Autodesk Fusion 360 part; units mm, degrees
(part 2 of 3)
sketch "X02_add_gear (2)" plane through (-4.75, 0, 0) normal (1, 0, 0) x (0, 0, -1) in component "OuterKnuckle_R"
  line L0 (-54.905, -30.601) -> (-49.6957, -2.7337)
  arc A0 (-49.6957, -2.7337) -> (-50.6618, -2.5703) centre (-54.905, -30.601) ccw
  line L1 (-50.6618, -2.5703) -> (-50.6013, -2.1703)
  spline S0 degree 5 poles (-50.6013, -2.1703) (-50.5993, -2.1455) (-50.5958, -2.0959) (-50.5916, -2.0214) (-50.5878, -1.9219) (-50.5864, -1.7973) (-50.5883, -1.6723) (-50.5934, -1.547) (-50.6015, -1.4215) (-50.6125, -1.2957) (-50.626, -1.1698) (-50.6418, -1.0437) (-50.6597, -0.9176) (-50.6793, -0.7914) (-50.7007, -0.6651) (-50.7237, -0.5388) (-50.7485, -0.4126) (-50.7749, -0.2863) (-50.8029, -0.1599) (-50.8327, -0.0336) (-50.864, 0.0927) (-50.8969, 0.219) (-50.9313, 0.3452) (-50.9671, 0.4714) (-51.0044, 0.5975) (-51.043, 0.7236) (-51.0829, 0.8496) (-51.1242, 0.9755) (-51.1669, 1.1013) (-51.2109, 1.227) (-51.2562, 1.3526) (-51.2934, 1.453) (-51.322, 1.5283) (-51.3413, 1.5784) (-51.351, 1.6035) knots 0 0 0 0 0 0 0.033333 0.066667 0.1 0.133333 0.166667 0.2 0.233333 0.266667 0.3 0.333333 0.366667 0.4 0.433333 0.466667 0.5 0.533333 0.566667 0.6 0.633333 0.666667 0.7 0.733333 0.766667 0.8 0.833333 0.866667 0.9 0.933333 0.966667 1 1 1 1 1 1
  arc A1 (-51.351, 1.6035) -> (-52.481, 1.7082) centre (-54.905, -30.601) ccw
  spline S1 degree 5 poles (-52.481, 1.7082) (-52.4951, 1.6853) (-52.5233, 1.6396) (-52.5652, 1.5708) (-52.6203, 1.479) (-52.6879, 1.3638) (-52.7542, 1.2484) (-52.8192, 1.1325) (-52.883, 1.0164) (-52.9454, 0.8999) (-53.0065, 0.7831) (-53.0663, 0.6659) (-53.1247, 0.5485) (-53.1817, 0.4307) (-53.2372, 0.3126) (-53.2912, 0.1942) (-53.3437, 0.0755) (-53.3945, -0.0435) (-53.4437, -0.1628) (-53.4912, -0.2824) (-53.537, -0.4023) (-53.5812, -0.5225) (-53.6237, -0.6429) (-53.6644, -0.7637) (-53.7032, -0.8847) (-53.7396, -1.006) (-53.7735, -1.1276) (-53.8046, -1.2495) (-53.8326, -1.3717) (-53.8574, -1.4942) (-53.8789, -1.617) (-53.8935, -1.7155) (-53.903, -1.7895) (-53.9087, -1.8389) (-53.9113, -1.8636) knots 0 0 0 0 0 0 0.033333 0.066667 0.1 0.133333 0.166667 0.2 0.233333 0.266667 0.3 0.333333 0.366667 0.4 0.433333 0.466667 0.5 0.533333 0.566667 0.6 0.633333 0.666667 0.7 0.733333 0.766667 0.8 0.833333 0.866667 0.9 0.933333 0.966667 1 1 1 1 1 1
  line L2 (-53.9113, -1.8636) -> (-53.9253, -2.2679)
  arc A2 (-53.9253, -2.2679) -> (-55.8847, -2.2679) centre (-54.905, -30.601) ccw
  line L3 (-55.8847, -2.2679) -> (-55.8987, -1.8636)
  spline S2 degree 5 poles (-55.8987, -1.8636) (-55.9013, -1.8389) (-55.907, -1.7895) (-55.9165, -1.7155) (-55.9311, -1.617) (-55.9526, -1.4942) (-55.9774, -1.3717) (-56.0054, -1.2495) (-56.0365, -1.1276) (-56.0704, -1.006) (-56.1068, -0.8847) (-56.1456, -0.7637) (-56.1863, -0.6429) (-56.2288, -0.5225) (-56.273, -0.4023) (-56.3188, -0.2824) (-56.3663, -0.1628) (-56.4155, -0.0435) (-56.4663, 0.0755) (-56.5188, 0.1942) (-56.5728, 0.3126) (-56.6283, 0.4307) (-56.6853, 0.5485) (-56.7437, 0.6659) (-56.8035, 0.7831) (-56.8646, 0.8999) (-56.927, 1.0164) (-56.9908, 1.1325) (-57.0558, 1.2484) (-57.1221, 1.3638) (-57.1897, 1.479) (-57.2448, 1.5708) (-57.2867, 1.6396) (-57.3149, 1.6853) (-57.329, 1.7082) knots 0 0 0 0 0 0 0.033333 0.066667 0.1 0.133333 0.166667 0.2 0.233333 0.266667 0.3 0.333333 0.366667 0.4 0.433333 0.466667 0.5 0.533333 0.566667 0.6 0.633333 0.666667 0.7 0.733333 0.766667 0.8 0.833333 0.866667 0.9 0.933333 0.966667 1 1 1 1 1 1
  arc A3 (-57.329, 1.7082) -> (-58.459, 1.6035) centre (-54.905, -30.601) ccw
  spline S3 degree 5 poles (-58.459, 1.6035) (-58.4687, 1.5784) (-58.488, 1.5283) (-58.5166, 1.453) (-58.5538, 1.3526) (-58.5991, 1.227) (-58.6431, 1.1013) (-58.6858, 0.9755) (-58.7271, 0.8496) (-58.767, 0.7236) (-58.8056, 0.5975) (-58.8429, 0.4714) (-58.8787, 0.3452) (-58.9131, 0.219) (-58.946, 0.0927) (-58.9773, -0.0336) (-59.0071, -0.1599) (-59.0351, -0.2863) (-59.0615, -0.4126) (-59.0863, -0.5388) (-59.1093, -0.6651) (-59.1307, -0.7914) (-59.1503, -0.9176) (-59.1682, -1.0437) (-59.184, -1.1698) (-59.1975, -1.2957) (-59.2085, -1.4215) (-59.2166, -1.547) (-59.2217, -1.6723) (-59.2236, -1.7973) (-59.2222, -1.9219) (-59.2184, -2.0214) (-59.2142, -2.0959) (-59.2107, -2.1455) (-59.2087, -2.1703) knots 0 0 0 0 0 0 0.033333 0.066667 0.1 0.133333 0.166667 0.2 0.233333 0.266667 0.3 0.333333 0.366667 0.4 0.433333 0.466667 0.5 0.533333 0.566667 0.6 0.633333 0.666667 0.7 0.733333 0.766667 0.8 0.833333 0.866667 0.9 0.933333 0.966667 1 1 1 1 1 1
  line L4 (-59.2087, -2.1703) -> (-59.1482, -2.5703)
  arc A4 (-59.1482, -2.5703) -> (-61.0742, -2.9304) centre (-54.905, -30.601) ccw
  line L5 (-61.0742, -2.9304) -> (-61.1622, -2.5355)
  spline S4 degree 5 poles (-61.1622, -2.5355) (-61.1694, -2.5117) (-61.184, -2.4642) (-61.207, -2.3932) (-61.2394, -2.299) (-61.2832, -2.1823) (-61.3301, -2.0664) (-61.38, -1.9514) (-61.433, -1.8373) (-61.4886, -1.724) (-61.5467, -1.6115) (-61.607, -1.4996) (-61.6692, -1.3884) (-61.7332, -1.2779) (-61.7987, -1.1679) (-61.8658, -1.0584) (-61.9345, -0.9496) (-62.0047, -0.8414) (-62.0765, -0.7337) (-62.1499, -0.6267) (-62.2247, -0.5202) (-62.301, -0.4144) (-62.3787, -0.3091) (-62.4577, -0.2043) (-62.538, -0.1002) (-62.6195, 0.0034) (-62.7023, 0.1065) (-62.7863, 0.209) (-62.8715, 0.3109) (-62.9579, 0.4122) (-63.0455, 0.5129) (-63.1166, 0.5931) (-63.1703, 0.653) (-63.2064, 0.6928) (-63.2246, 0.7127) knots 0 0 0 0 0 0 0.033333 0.066667 0.1 0.133333 0.166667 0.2 0.233333 0.266667 0.3 0.333333 0.366667 0.4 0.433333 0.466667 0.5 0.533333 0.566667 0.6 0.633333 0.666667 0.7 0.733333 0.766667 0.8 0.833333 0.866667 0.9 0.933333 0.966667 1 1 1 1 1 1
  arc A5 (-63.2246, 0.7127) -> (-64.3161, 0.4021) centre (-54.905, -30.601) ccw
  spline S5 degree 5 poles (-64.3161, 0.4021) (-64.321, 0.3757) (-64.3308, 0.3228) (-64.345, 0.2436) (-64.3632, 0.138) (-64.3846, 0.0062) (-64.4047, -0.1254) (-64.4236, -0.2569) (-64.441, -0.3882) (-64.4572, -0.5194) (-64.4719, -0.6504) (-64.4854, -0.7812) (-64.4974, -0.9119) (-64.508, -1.0423) (-64.5171, -1.1725) (-64.5247, -1.3024) (-64.5307, -1.432) (-64.5351, -1.5613) (-64.5379, -1.6903) (-64.539, -1.819) (-64.5384, -1.9474) (-64.5362, -2.0754) (-64.5324, -2.2031) (-64.5267, -2.3304) (-64.5191, -2.4572) (-64.5093, -2.5835) (-64.4969, -2.7091) (-64.4819, -2.834) (-64.4638, -2.958) (-64.4427, -3.0812) (-64.4184, -3.2035) (-64.3965, -3.3006) (-64.3786, -3.3731) (-64.366, -3.4212) (-64.3596, -3.4452) knots 0 0 0 0 0 0 0.033333 0.066667 0.1 0.133333 0.166667 0.2 0.233333 0.266667 0.3 0.333333 0.366667 0.4 0.433333 0.466667 0.5 0.533333 0.566667 0.6 0.633333 0.666667 0.7 0.733333 0.766667 0.8 0.833333 0.866667 0.9 0.933333 0.966667 1 1 1 1 1 1
  line L6 (-64.3596, -3.4452) -> (-64.2266, -3.8273)
  arc A6 (-64.2266, -3.8273) -> (-66.0536, -4.5351) centre (-54.905, -30.601) ccw
  line L7 (-66.0536, -4.5351) -> (-66.2127, -4.1631)
  spline S6 degree 5 poles (-66.2127, -4.1631) (-66.2241, -4.141) (-66.2473, -4.097) (-66.2828, -4.0314) (-66.332, -3.9449) (-66.3965, -3.8381) (-66.4639, -3.7329) (-66.5341, -3.629) (-66.6071, -3.5266) (-66.6827, -3.4254) (-66.7605, -3.3255) (-66.8403, -3.2266) (-66.9219, -3.1288) (-67.005, -3.0318) (-67.0896, -2.9357) (-67.1757, -2.8405) (-67.2632, -2.7461) (-67.3521, -2.6526) (-67.4425, -2.56) (-67.5343, -2.4683) (-67.6274, -2.3774) (-67.7219, -2.2874) (-67.8176, -2.1981) (-67.9145, -2.1097) (-68.0125, -2.022) (-68.1117, -1.9352) (-68.212, -1.8491) (-68.3134, -1.7638) (-68.4159, -1.6793) (-68.5195, -1.5956) (-68.6241, -1.5126) (-68.7086, -1.4469) (-68.7725, -1.3979) (-68.8153, -1.3654) (-68.8368, -1.3492) knots 0 0 0 0 0 0 0.033333 0.066667 0.1 0.133333 0.166667 0.2 0.233333 0.266667 0.3 0.333333 0.366667 0.4 0.433333 0.466667 0.5 0.533333 0.566667 0.6 0.633333 0.666667 0.7 0.733333 0.766667 0.8 0.833333 0.866667 0.9 0.933333 0.966667 1 1 1 1 1 1
  arc A7 (-68.8368, -1.3492) -> (-69.8526, -1.8551) centre (-54.905, -30.601) ccw
  spline S7 degree 5 poles (-69.8526, -1.8551) (-69.8526, -1.882) (-69.8525, -1.9357) (-69.8519, -2.0162) (-69.8504, -2.1233) (-69.8473, -2.2568) (-69.8429, -2.3899) (-69.8372, -2.5226) (-69.8302, -2.6549) (-69.822, -2.7868) (-69.8125, -2.9183) (-69.8016, -3.0494) (-69.7894, -3.18) (-69.7759, -3.3101) (-69.7609, -3.4398) (-69.7445, -3.5689) (-69.7266, -3.6974) (-69.7072, -3.8253) (-69.6862, -3.9526) (-69.6636, -4.0793) (-69.6395, -4.2054) (-69.6138, -4.3308) (-69.5865, -4.4556) (-69.5576, -4.5797) (-69.5268, -4.703) (-69.4939, -4.8253) (-69.4587, -4.9465) (-69.421, -5.0665) (-69.3805, -5.1851) (-69.3371, -5.3024) (-69.2907, -5.4181) (-69.2513, -5.5095) (-69.2204, -5.5775) (-69.1992, -5.6224) (-69.1885, -5.6449) knots 0 0 0 0 0 0 0.033333 0.066667 0.1 0.133333 0.166667 0.2 0.233333 0.266667 0.3 0.333333 0.366667 0.4 0.433333 0.466667 0.5 0.533333 0.566667 0.6 0.633333 0.666667 0.7 0.733333 0.766667 0.8 0.833333 0.866667 0.9 0.933333 0.966667 1 1 1 1 1 1
  line L8 (-69.1885, -5.6449) -> (-68.9875, -5.996)
  arc A8 (-68.9875, -5.996) -> (-70.6534, -7.0275) centre (-54.905, -30.601) ccw
  line L9 (-70.6534, -7.0275) -> (-70.8781, -6.691)
  spline S8 degree 5 poles (-70.8781, -6.691) (-70.8934, -6.6714) (-70.9242, -6.6324) (-70.9713, -6.5745) (-71.0355, -6.4985) (-71.1185, -6.4054) (-71.2041, -6.3143) (-71.2922, -6.2251) (-71.3828, -6.1378) (-71.4756, -6.0523) (-71.5705, -5.9683) (-71.6671, -5.8858) (-71.7653, -5.8046) (-71.8648, -5.7246) (-71.9657, -5.6457) (-72.0678, -5.5679) (-72.1711, -5.4912) (-72.2757, -5.4157) (-72.3816, -5.3412) (-72.4886, -5.2679) (-72.5969, -5.1957) (-72.7063, -5.1245) (-72.8167, -5.0544) (-72.9282, -4.9853) (-73.0407, -4.9172) (-73.1542, -4.85) (-73.2686, -4.7838) (-73.3839, -4.7186) (-73.5002, -4.6544) (-73.6174, -4.5911) (-73.7355, -4.5288) (-73.8307, -4.4797) (-73.9024, -4.4433) (-73.9505, -4.4192) (-73.9746, -4.4073) knots 0 0 0 0 0 0 0.033333 0.066667 0.1 0.133333 0.166667 0.2 0.233333 0.266667 0.3 0.333333 0.366667 0.4 0.433333 0.466667 0.5 0.533333 0.566667 0.6 0.633333 0.666667 0.7 0.733333 0.766667 0.8 0.833333 0.866667 0.9 0.933333 0.966667 1 1 1 1 1 1
  arc A9 (-73.9746, -4.4073) -> (-74.8802, -5.0912) centre (-54.905, -30.601) ccw
  spline S9 degree 5 poles (-74.8802, -5.0912) (-74.8752, -5.1176) (-74.8652, -5.1704) (-74.8499, -5.2494) (-74.8287, -5.3544) (-74.8011, -5.485) (-74.7723, -5.6151) (-74.7423, -5.7445) (-74.7112, -5.8732) (-74.6789, -6.0014) (-74.6453, -6.1289) (-74.6106, -6.2557) (-74.5746, -6.3819) (-74.5374, -6.5073) (-74.4988, -6.632) (-74.459, -6.7559) (-74.4178, -6.8789) (-74.3752, -7.0011) (-74.3311, -7.1224) (-74.2857, -7.2428) (-74.2388, -7.3623) (-74.1905, -7.4809) (-74.1408, -7.5985) (-74.0895, -7.7152) (-74.0366, -7.8307) (-73.9818, -7.9449) (-73.9249, -8.0576) (-73.8658, -8.1686) (-73.8041, -8.2778) (-73.7399, -8.385) (-73.6731, -8.4903) (-73.6176, -8.5729) (-73.5747, -8.634) (-73.5456, -8.6743) (-73.531, -8.6944) knots 0 0 0 0 0 0 0.033333 0.066667 0.1 0.133333 0.166667 0.2 0.233333 0.266667 0.3 0.333333 0.366667 0.4 0.433333 0.466667 0.5 0.533333 0.566667 0.6 0.633333 0.666667 0.7 0.733333 0.766667 0.8 0.833333 0.866667 0.9 0.933333 0.966667 1 1 1 1 1 1
  line L10 (-73.531, -8.6944) -> (-73.2689, -9.0026)
  arc A10 (-73.2689, -9.0026) -> (-74.7169, -10.3226) centre (-54.905, -30.601) ccw
  line L11 (-74.7169, -10.3226) -> (-74.9996, -10.0332)
  spline S10 degree 5 poles (-74.9996, -10.0332) (-75.0182, -10.0168) (-75.0557, -9.9841) (-75.1126, -9.9358) (-75.1897, -9.8728) (-75.2884, -9.7966) (-75.3892, -9.7228) (-75.4922, -9.6513) (-75.5973, -9.5822) (-75.7043, -9.5151) (-75.8129, -9.45) (-75.9231, -9.3867) (-76.0345, -9.3249) (-76.1471, -9.2645) (-76.2607, -9.2055) (-76.3754, -9.1478) (-76.491, -9.0914) (-76.6077, -9.0364) (-76.7254, -8.9826) (-76.8442, -8.9303) (-76.9639, -8.8792) (-77.0845, -8.8293) (-77.2059, -8.7807) (-77.3282, -8.7332) (-77.4513, -8.6869) (-77.5752, -8.6417) (-77.6998, -8.5977) (-77.8251, -8.5548) (-77.9512, -8.513) (-78.0781, -8.4724) (-78.2056, -8.4328) (-78.3082, -8.4021) (-78.3854, -8.3795) (-78.4371, -8.3646) (-78.4629, -8.3573) knots 0 0 0 0 0 0 0.033333 0.066667 0.1 0.133333 0.166667 0.2 0.233333 0.266667 0.3 0.333333 0.366667 0.4 0.433333 0.466667 0.5 0.533333 0.566667 0.6 0.633333 0.666667 0.7 0.733333 0.766667 0.8 0.833333 0.866667 0.9 0.933333 0.966667 1 1 1 1 1 1
  arc A11 (-78.4629, -8.3573) -> (-79.2275, -9.1959) centre (-54.905, -30.601) ccw
  spline S11 degree 5 poles (-79.2275, -9.1959) (-79.2178, -9.221) (-79.1982, -9.2711) (-79.1686, -9.3459) (-79.1285, -9.4452) (-79.0774, -9.5686) (-79.0252, -9.6911) (-78.972, -9.8128) (-78.9177, -9.9337) (-78.8623, -10.0537) (-78.8059, -10.1729) (-78.7485, -10.2911) (-78.6899, -10.4085) (-78.6303, -10.525) (-78.5695, -10.6405) (-78.5076, -10.7549) (-78.4445, -10.8683) (-78.3801, -10.9806) (-78.3145, -11.0917) (-78.2477, -11.2017) (-78.1797, -11.3105) (-78.1104, -11.4182) (-78.0399, -11.5247) (-77.9681, -11.63) (-77.8949, -11.7338) (-77.82, -11.836) (-77.7434, -11.9363) (-77.6649, -12.0346) (-77.5842, -12.1306) (-77.5014, -12.2242) (-77.4164, -12.3154) (-77.3466, -12.3864) (-77.2933, -12.4386) (-77.2573, -12.4729) (-77.2391, -12.4899) knots 0 0 0 0 0 0 0.033333 0.066667 0.1 0.133333 0.166667 0.2 0.233333 0.266667 0.3 0.333333 0.366667 0.4 0.433333 0.466667 0.5 0.533333 0.566667 0.6 0.633333 0.666667 0.7 0.733333 0.766667 0.8 0.833333 0.866667 0.9 0.933333 0.966667 1 1 1 1 1 1
  line L12 (-77.2391, -12.4899) -> (-76.9249, -12.7447)
  arc A12 (-76.9249, -12.7447) -> (-78.1057, -14.3083) centre (-54.905, -30.601) ccw
  line L13 (-78.1057, -14.3083) -> (-78.4368, -14.0758)
  spline S12 degree 5 poles (-78.4368, -14.0758) (-78.4581, -14.063) (-78.5009, -14.0378) (-78.5657, -14.0008) (-78.6531, -13.9531) (-78.7641, -13.8962) (-78.8768, -13.8422) (-78.9912, -13.7909) (-79.1072, -13.7422) (-79.2247, -13.696) (-79.3434, -13.652) (-79.4633, -13.61) (-79.5842, -13.5697) (-79.7059, -13.531) (-79.8285, -13.4939) (-79.9518, -13.4582) (-80.0759, -13.4241) (-80.2007, -13.3914) (-80.3263, -13.3602) (-80.4526, -13.3306) (-80.5796, -13.3023) (-80.7073, -13.2755) (-80.8357, -13.25) (-80.9646, -13.2258) (-81.0941, -13.2029) (-81.2242, -13.1813) (-81.3548, -13.1609) (-81.4859, -13.1417) (-81.6175, -13.1239) (-81.7496, -13.1072) (-81.8822, -13.0918) (-81.9887, -13.0804) (-82.0688, -13.0724) (-82.1223, -13.0673) (-82.1491, -13.0648) knots 0 0 0 0 0 0 0.033333 0.066667 0.1 0.133333 0.166667 0.2 0.233333 0.266667 0.3 0.333333 0.366667 0.4 0.433333 0.466667 0.5 0.533333 0.566667 0.6 0.633333 0.666667 0.7 0.733333 0.766667 0.8 0.833333 0.866667 0.9 0.933333 0.966667 1 1 1 1 1 1
  arc A13 (-82.1491, -13.0648) -> (-82.7465, -14.0297) centre (-54.905, -30.601) ccw
  spline S13 degree 5 poles (-82.7465, -14.0297) (-82.7324, -14.0525) (-82.704, -14.0981) (-82.6611, -14.1662) (-82.6034, -14.2565) (-82.5305, -14.3683) (-82.4567, -14.4792) (-82.382, -14.589) (-82.3064, -14.6979) (-82.23, -14.8057) (-82.1526, -14.9125) (-82.0744, -15.0182) (-81.9953, -15.1228) (-81.9153, -15.2263) (-81.8343, -15.3287) (-81.7524, -15.4298) (-81.6695, -15.5297) (-81.5857, -15.6282) (-81.5008, -15.7254) (-81.4149, -15.8212) (-81.328, -15.9157) (-81.2401, -16.0088) (-81.1513, -16.1006) (-81.0613, -16.1909) (-80.9703, -16.2794) (-80.8779, -16.3661) (-80.7842, -16.4507) (-80.6889, -16.5328) (-80.592, -16.6123) (-80.4934, -16.6892) (-80.3931, -16.7632) (-80.3114, -16.8202) (-80.2494, -16.8616) (-80.2077, -16.8887) (-80.1868, -16.9021) knots 0 0 0 0 0 0 0.033333 0.066667 0.1 0.133333 0.166667 0.2 0.233333 0.266667 0.3 0.333333 0.366667 0.4 0.433333 0.466667 0.5 0.533333 0.566667 0.6 0.633333 0.666667 0.7 0.733333 0.766667 0.8 0.833333 0.866667 0.9 0.933333 0.966667 1 1 1 1 1 1
  line L14 (-80.1868, -16.9021) -> (-79.831, -17.0949)
  arc A14 (-79.831, -17.0949) -> (-80.2829, -17.9643) centre (-54.905, -30.601) ccw
  line L15 (-80.2829, -17.9643) -> (-54.905, -30.601)
  point P0 (-50.5936, -1.5571)
  point P1 (-50.6577, -0.9338)
  point P2 (-50.7714, -0.3044)
  point P3 (-50.9272, 0.3291)
  point P4 (-51.1212, 0.9655)
  point P5 (-52.824, 1.1233)
  point P6 (-53.1317, 0.5334)
  point P7 (-53.4012, -0.0607)
  point P8 (-53.6286, -0.6585)
  point P9 (-53.8062, -1.2594)
  point P10 (-56.0038, -1.2594)
  point P11 (-56.1814, -0.6585)
  point P12 (-56.4088, -0.0607)
  point P13 (-56.6783, 0.5334)
  point P14 (-56.986, 1.1233)
  point P15 (-58.6888, 0.9655)
  point P16 (-58.8828, 0.3291)
  point P17 (-59.0386, -0.3044)
  point P18 (-59.1523, -0.9338)
  point P19 (-59.2164, -1.5571)
  point P20 (-61.3766, -1.9609)
  point P21 (-61.6616, -1.4028)
  point P22 (-61.9949, -0.857)
  point P23 (-62.3691, -0.3226)
  point P24 (-62.7799, 0.2007)
  point P25 (-64.4247, -0.2673)
  point P26 (-64.4985, -0.9284)
  point P27 (-64.5352, -1.5798)
  point P28 (-64.5313, -2.2193)
  point P29 (-64.4798, -2.8438)
  point P30 (-66.529, -3.6377)
  point P31 (-66.9117, -3.1415)
  point P32 (-67.3396, -2.6662)
  point P33 (-67.8056, -2.2096)
  point P34 (-68.3056, -1.7708)
  point P35 (-69.8364, -2.533)
  point P36 (-69.7874, -3.1965)
  point P37 (-69.7039, -3.8435)
  point P38 (-69.5825, -4.4714)
  point P39 (-69.4171, -5.0758)
  point P40 (-71.2856, -6.2327)
  point P41 (-71.7529, -5.8153)
  point P42 (-72.2609, -5.4267)
  point P43 (-72.8029, -5.0635)
  point P44 (-73.375, -4.724)
  point P45 (-74.7396, -5.7545)
  point P46 (-74.5696, -6.3977)
  point P47 (-74.3686, -7.0184)
  point P48 (-74.1339, -7.6133)
  point P49 (-73.8603, -8.177)
  point P50 (-75.4843, -9.6576)
  point P51 (-76.0204, -9.3331)
  point P52 (-76.5912, -9.0445)
  point P53 (-77.1906, -8.7871)
  point P54 (-77.8154, -8.5584)
  point P55 (-78.9674, -9.8222)
  point P56 (-78.6821, -10.4232)
  point P57 (-78.3705, -10.9963)
  point P58 (-78.0305, -11.538)
  point P59 (-77.6579, -12.0419)
  point P60 (-78.9823, -13.7956)
  point P61 (-79.5689, -13.5752)
  point P62 (-80.1829, -13.3964)
  point P63 (-80.8195, -13.2535)
  point P64 (-81.4756, -13.1435)
  point P65 (-82.3758, -14.5975)
  point P66 (-81.9849, -15.1358)
  point P67 (-81.5733, -15.6419)
  point P68 (-81.1395, -16.1119)
  point P69 (-80.6807, -16.5387)
extrude "X02_add_gear (1)'" add sketch "X02_add_gear (2)" along normal blind 9.5 bodies 8 in component "OuterKnuckle_R"
sketch "X03_add_wedge (2)" plane through (-4.75, 0, 0) normal (1, 0, 0) x (0, 0, -1) in component "OuterKnuckle_R"
  line L0 (-54.905, -30.601) -> (-50.495, -7.0096)
  arc A0 (-50.495, -7.0096) -> (-78.1921, -24.7949) centre (-54.905, -30.601) ccw
  line L1 (-78.1921, -24.7949) -> (-54.905, -30.601)
extrude "X03_add_wedge (1)'" add sketch "X03_add_wedge (2)" along normal blind 9.5 bodies 8 in component "OuterKnuckle_R"
sketch "X04_cut_kidney (2)" plane through (-4.75, 0, 0) normal (1, 0, 0) x (0, 0, -1) in component "OuterKnuckle_R"
  arc A0 (-61.6876, -10.9383) -> (-72.8524, -20.0883) centre (-54.905, -30.601) ccw
  arc A1 (-72.8524, -20.0883) -> (-69.8324, -21.8573) centre (-71.3424, -20.9728) ccw
  arc A2 (-60.5463, -14.2469) -> (-69.8324, -21.8573) centre (-54.905, -30.601) ccw
  arc A3 (-60.5463, -14.2469) -> (-61.6876, -10.9383) centre (-61.117, -12.5926) ccw
extrude "X04_cut_kidney (1)'" cut sketch "X04_cut_kidney (2)" along normal blind 9.5 bodies 8 in component "OuterKnuckle_R"
sketch "X05_cut_circle (2)" plane through (-4.75, 0, 0) normal (1, 0, 0) x (0, 0, -1) in component "OuterKnuckle_R"
  circle A0 centre (-54.905, -30.601) radius 1.65
extrude "X05_cut_circle (1)'" cut sketch "X05_cut_circle (2)" along normal blind 9.5 bodies 8 in component "OuterKnuckle_R"
sketch "X06_cut_circle (3)" plane through (-4.75, 0, 0) normal (1, 0, 0) x (0, 0, -1) in component "OuterKnuckle_R"
  circle A0 centre (-51.2999, -62.1457) radius 1.65
extrude "X06_cut_circle (1)''" cut sketch "X06_cut_circle (3)" along normal blind 9.5 bodies 8 in component "OuterKnuckle_R"
sketch "X07_cut_circle (4)" plane through (-4.75, 0, 0) normal (1, 0, 0) x (0, 0, -1) in component "OuterKnuckle_R"
  circle A0 centre (-60.539, -65.9718) radius 1.65
extrude "X07_cut_circle (1)'''" cut sketch "X07_cut_circle (4)" along normal blind 9.5 bodies 8 in component "OuterKnuckle_R"
ref_plane "WorkPlane1" through (-12, 0, 0) normal (1, 0, 0) x (0, 1, 0) in component "OuterFinger"
sketch "X00_add_hull (3)" plane through (-12, 0, 0) normal (1, 0, 0) x (0, 0, -1) in component "OuterFinger"
  line L0 (-128.7903, -101.2714) -> (-48.5106, -69.1077)
  arc A0 (-48.5106, -69.1077) -> (-54.2495, -55.25) centre (-51.2999, -62.1457) ccw
  line L1 (-54.2495, -55.25) -> (-133.764, -89.2614)
  arc A1 (-133.764, -89.2614) -> (-128.7903, -101.2714) centre (-131.2077, -95.2377) ccw
extrude "X00_add_hull (1)''" add sketch "X00_add_hull (3)" along normal blind 24 separate body makes body 9 in component "OuterFinger"
ref_plane "WorkPlane2" through (-5, 0, 0) normal (1, 0, 0) x (0, 1, 0) in component "OuterFinger"
sketch "X01_cut_hull" plane through (-5, 0, 0) normal (1, 0, 0) x (0, 0, -1) in component "OuterFinger"
  line L0 (-58.052, -71.9772) -> (-48.8129, -68.1511)
  arc A0 (-48.8129, -68.1511) -> (-44.8083, -61.8159) centre (-51.2999, -62.1457) ccw
  line L1 (-44.8083, -61.8159) -> (-46.4159, -30.1697)
  arc A1 (-46.4159, -30.1697) -> (-63.3607, -29.7348) centre (-54.905, -30.601) ccw
  line L2 (-63.3607, -29.7348) -> (-67.0052, -65.3094)
  arc A2 (-67.0052, -65.3094) -> (-58.052, -71.9772) centre (-60.539, -65.9718) ccw
extrude "X01_cut_hull (1)" cut sketch "X01_cut_hull" along normal blind 10 bodies 9 in component "OuterFinger"
ref_plane "WorkPlane3" through (-7.75, 0, 0) normal (1, 0, 0) x (0, 1, 0) in component "OuterFinger"
sketch "X02_cut_hull" plane through (-7.75, 0, 0) normal (1, 0, 0) x (0, 0, -1) in component "OuterFinger"
  line L0 (-125.5305, -101.2924) -> (-118.261, -94.4762)
  arc A0 (-118.261, -94.4762) -> (-128.3351, -82.5908) centre (-123.5962, -88.7862) ccw
  line L1 (-128.3351, -82.5908) -> (-136.2503, -88.6451)
  arc A1 (-136.2503, -88.6451) -> (-125.5305, -101.2924) centre (-131.2077, -95.2377) ccw
extrude "X02_cut_hull (1)" cut sketch "X02_cut_hull" along normal blind 15.5 bodies 9 in component "OuterFinger"
sketch "X03_cut_circle" plane through (-12, 0, 0) normal (1, 0, 0) x (0, 0, -1) in component "OuterFinger"
  circle A0 centre (-51.2999, -62.1457) radius 1.65
extrude "X03_cut_circle (1)" cut sketch "X03_cut_circle" along normal blind 24 bodies 9 in component "OuterFinger"
sketch "X04_cut_circle" plane through (-12, 0, 0) normal (1, 0, 0) x (0, 0, -1) in component "OuterFinger"
  circle A0 centre (-60.539, -65.9718) radius 1.65
extrude "X04_cut_circle (1)" cut sketch "X04_cut_circle" along normal blind 24 bodies 9 in component "OuterFinger"
sketch "X05_cut_circle (3)" plane through (-12, 0, 0) normal (1, 0, 0) x (0, 0, -1) in component "OuterFinger"
  circle A0 centre (-131.2077, -95.2377) radius 1.65
extrude "X05_cut_circle (1)''" cut sketch "X05_cut_circle (3)" along normal blind 24 bodies 9 in component "OuterFinger"
ref_plane "WorkPlane1" through (-7.5, 0, 0) normal (1, 0, 0) x (0, 1, 0) in component "InnerFinger"
sketch "X00_add_hull (4)" plane through (-7.5, 0, 0) normal (1, 0, 0) x (0, 0, -1) in component "InnerFinger"
  line L0 (-125.5695, -93.1857) -> (-132.0845, -75.2847)
  arc A0 (-132.0845, -75.2847) -> (-143.3609, -79.3887) centre (-137.7227, -77.3367) ccw
  line L1 (-143.3609, -79.3887) -> (-136.8459, -97.2897)
  arc A1 (-136.8459, -97.2897) -> (-125.5695, -93.1857) centre (-131.2077, -95.2377) ccw
extrude "X00_add_hull (1)'''" add sketch "X00_add_hull (4)" along normal blind 15 separate body makes body 10 in component "InnerFinger"
sketch "X01_add_hull (3)" plane through (-7.5, 0, 0) normal (1, 0, 0) x (0, 0, -1) in component "InnerFinger"
  line L0 (-175.7077, -83.3377) -> (-137.721, -83.3267)
  arc A0 (-137.721, -83.3267) -> (-137.7229, -71.3467) centre (-137.7227, -77.3367) ccw
  line L1 (-137.7229, -71.3467) -> (-175.7077, -71.3477)
  line L2 (-175.7077, -71.3477) -> (-175.7077, -83.3377)
extrude "X01_add_hull (1)''" add sketch "X01_add_hull (3)" along normal blind 15 bodies 10 in component "InnerFinger"
sketch "X02_cut_circle (3)" plane through (-7.5, 0, 0) normal (1, 0, 0) x (0, 0, -1) in component "InnerFinger"
  circle A0 centre (-131.2077, -95.2377) radius 1.65
extrude "X02_cut_circle (1)''" cut sketch "X02_cut_circle (3)" along normal blind 15 bodies 10 in component "InnerFinger"
sketch "X03_cut_circle (2)" plane through (-7.5, 0, 0) normal (1, 0, 0) x (0, 0, -1) in component "InnerFinger"
  circle A0 centre (-137.7227, -77.3367) radius 1.65
extrude "X03_cut_circle (1)'" cut sketch "X03_cut_circle (2)" along normal blind 15 bodies 10 in component "InnerFinger"
ref_plane "WorkPlane2" through (0, -83.4377, 0) normal (0, 1, 0) x (0, 0, 1) in component "InnerFinger"
sketch "Y00_cut_circle" plane through (0, -83.4377, 0) normal (0, 1, 0) x (1, 0, 0) in component "InnerFinger"
  circle A0 centre (0, -151.2077) radius 1.7
extrude "Y00_cut_circle (1)" cut sketch "Y00_cut_circle" along normal blind 12.2 bodies 10 in component "InnerFinger"
sketch "Y01_cut_circle" plane through (0, -83.4377, 0) normal (0, 1, 0) x (1, 0, 0) in component "InnerFinger"
  circle A0 centre (0, -165.2077) radius 1.7
extrude "Y01_cut_circle (1)" cut sketch "Y01_cut_circle" along normal blind 12.2 bodies 10 in component "InnerFinger"
ref_plane "WorkPlane1" through (-7, 0, 0) normal (1, 0, 0) x (0, 1, 0) in component "Fingertip"
sketch "X00_add_poly" plane through (-7, 0, 0) normal (1, 0, 0) x (0, 0, -1) in component "Fingertip"
  line L0 (-137.7077, -65.3377) -> (-213.7077, -65.3377)
  line L1 (-213.7077, -65.3377) -> (-213.7077, -71.3377)
  line L2 (-213.7077, -71.3377) -> (-137.7077, -71.3377)
  line L3 (-137.7077, -71.3377) -> (-137.7077, -65.3377)
extrude "X00_add_poly (1)" add sketch "X00_add_poly" along normal blind 14 separate body makes body 11 in component "Fingertip"
sketch "X01_add_poly" plane through (-7, 0, 0) normal (1, 0, 0) x (0, 0, -1) in component "Fingertip"
  line L0 (-175.9577, -71.3377) -> (-213.7077, -71.3377)
  line L1 (-213.7077, -71.3377) -> (-213.7077, -73.8377)
  line L2 (-213.7077, -73.8377) -> (-175.9577, -77.3377)
  line L3 (-175.9577, -77.3377) -> (-175.9577, -71.3377)
extrude "X01_add_poly (1)" add sketch "X01_add_poly" along normal blind 14 bodies 11 in component "Fingertip"
ref_plane "WorkPlane2" through (0, -71.4377, 0) normal (0, 1, 0) x (0, 0, 1) in component "Fingertip"
sketch "Y00_cut_hex" plane through (0, -71.4377, 0) normal (0, 1, 0) x (1, 0, 0) in component "Fingertip"
  line L0 (2.85, -152.8532) -> (0, -154.4986)
  line L1 (0, -154.4986) -> (-2.85, -152.8532)
  line L2 (-2.85, -152.8532) -> (-2.85, -149.5623)
  line L3 (-2.85, -149.5623) -> (0, -147.9168)
  line L4 (0, -147.9168) -> (2.85, -149.5623)
  line L5 (2.85, -149.5623) -> (2.85, -152.8532)
extrude "Y00_cut_hex (1)" cut sketch "Y00_cut_hex" along normal blind 4.3 bodies 11 in component "Fingertip"
sketch "Y01_cut_circle (2)" plane through (0, -71.4377, 0) normal (0, 1, 0) x (1, 0, 0) in component "Fingertip"
  circle A0 centre (0, -151.2077) radius 1.7
extrude "Y01_cut_circle (1)'" cut sketch "Y01_cut_circle (2)" along normal blind 4.3 bodies 11 in component "Fingertip"
sketch "Y02_cut_hex" plane through (0, -71.4377, 0) normal (0, 1, 0) x (1, 0, 0) in component "Fingertip"
  line L0 (2.85, -166.8532) -> (0, -168.4986)
  line L1 (0, -168.4986) -> (-2.85, -166.8532)
  line L2 (-2.85, -166.8532) -> (-2.85, -163.5623)
  line L3 (-2.85, -163.5623) -> (0, -161.9168)
  line L4 (0, -161.9168) -> (2.85, -163.5623)
  line L5 (2.85, -163.5623) -> (2.85, -166.8532)
extrude "Y02_cut_hex (1)" cut sketch "Y02_cut_hex" along normal blind 4.3 bodies 11 in component "Fingertip"
sketch "Y03_cut_circle" plane through (0, -71.4377, 0) normal (0, 1, 0) x (1, 0, 0) in component "Fingertip"
  circle A0 centre (0, -165.2077) radius 1.7
extrude "Y03_cut_circle (1)" cut sketch "Y03_cut_circle" along normal blind 4.3 bodies 11 in component "Fingertip"
ref_plane "WorkPlane1" through (0, 0, -35) normal (0, 0, 1) x (1, 0, 0) in component "SpacerB"
sketch "Z00_add_circle" plane through (0, 0, -35) normal (0, 0, 1) x (1, 0, 0) in component "SpacerB"
  circle A0 centre (0, 0) radius 37.5
extrude "Z00_add_circle (1)" add sketch "Z00_add_circle" along normal blind 35 separate body makes body 12 in component "SpacerB"
sketch "Z01_add_rect" plane through (0, 0, -35) normal (0, 0, 1) x (1, 0, 0) in component "SpacerB"
  line L0 (30, -15) -> (48.7, -15)
  line L1 (48.7, -15) -> (48.7, 15)
  line L2 (48.7, 15) -> (30, 15)
  line L3 (30, 15) -> (30, -15)
extrude "Z01_add_rect (1)" add sketch "Z01_add_rect" along normal blind 35 bodies 12 in component "SpacerB"
ref_plane "WorkPlane2" through (0, 0, -35.1) normal (0, 0, 1) x (1, 0, 0) in component "SpacerB"
sketch "Z02_cut_circle (2)" plane through (0, 0, -35.1) normal (0, 0, 1) x (1, 0, 0) in component "SpacerB"
  circle A0 centre (23.097, -9.5671) radius 3.3
extrude "Z02_cut_circle (1)'" cut sketch "Z02_cut_circle (2)" along normal blind 35.2 bodies 12 in component "SpacerB"
sketch "Z03_cut_circle (3)" plane through (0, 0, -35.1) normal (0, 0, 1) x (1, 0, 0) in component "SpacerB"
  circle A0 centre (9.5671, 23.097) radius 3.3
extrude "Z03_cut_circle (1)''" cut sketch "Z03_cut_circle (3)" along normal blind 35.2 bodies 12 in component "SpacerB"
sketch "Z04_cut_circle" plane through (0, 0, -35.1) normal (0, 0, 1) x (1, 0, 0) in component "SpacerB"
  circle A0 centre (-23.097, 9.5671) radius 3.3
extrude "Z04_cut_circle (1)" cut sketch "Z04_cut_circle" along normal blind 35.2 bodies 12 in component "SpacerB"
sketch "Z05_cut_circle" plane through (0, 0, -35.1) normal (0, 0, 1) x (1, 0, 0) in component "SpacerB"
  circle A0 centre (-9.5671, -23.097) radius 3.3
extrude "Z05_cut_circle (1)" cut sketch "Z05_cut_circle" along normal blind 35.2 bodies 12 in component "SpacerB"
ref_plane "WorkPlane3" through (0, 0, -9) normal (0, 0, 1) x (1, 0, 0) in component "SpacerB"
sketch "Z06_cut_circle (2)" plane through (0, 0, -9) normal (0, 0, 1) x (1, 0, 0) in component "SpacerB"
  circle A0 centre (23.097, -9.5671) radius 5.5
extrude "Z06_cut_circle (1)'" cut sketch "Z06_cut_circle (2)" along normal blind 9.1 bodies 12 in component "SpacerB"
sketch "Z07_cut_circle" plane through (0, 0, -9) normal (0, 0, 1) x (1, 0, 0) in component "SpacerB"
  circle A0 centre (9.5671, 23.097) radius 5.5
extrude "Z07_cut_circle (1)" cut sketch "Z07_cut_circle" along normal blind 9.1 bodies 12 in component "SpacerB"
sketch "Z08_cut_circle" plane through (0, 0, -9) normal (0, 0, 1) x (1, 0, 0) in component "SpacerB"
  circle A0 centre (-23.097, 9.5671) radius 5.5
extrude "Z08_cut_circle (1)" cut sketch "Z08_cut_circle" along normal blind 9.1 bodies 12 in component "SpacerB"
sketch "Z09_cut_circle (2)" plane through (0, 0, -9) normal (0, 0, 1) x (1, 0, 0) in component "SpacerB"
  circle A0 centre (-9.5671, -23.097) radius 5.5
extrude "Z09_cut_circle (1)'" cut sketch "Z09_cut_circle (2)" along normal blind 9.1 bodies 12 in component "SpacerB"
ref_plane "WorkPlane4" through (0, 0, -12) normal (0, 0, 1) x (1, 0, 0) in component "SpacerB"
sketch "Z10_cut_circle" plane through (0, 0, -12) normal (0, 0, 1) x (1, 0, 0) in component "SpacerB"
  circle A0 centre (26.8, 11.1) radius 1.7
extrude "Z10_cut_circle (1)" cut sketch "Z10_cut_circle" along normal blind 12.1 bodies 12 in component "SpacerB"
sketch "Z11_cut_circle" plane through (0, 0, -12) normal (0, 0, 1) x (1, 0, 0) in component "SpacerB"
  circle A0 centre (-11.1, 26.8) radius 1.7
extrude "Z11_cut_circle (1)" cut sketch "Z11_cut_circle" along normal blind 12.1 bodies 12 in component "SpacerB"
sketch "Z12_cut_circle (2)" plane through (0, 0, -12) normal (0, 0, 1) x (1, 0, 0) in component "SpacerB"
  circle A0 centre (-18, -28.5) radius 1.7
extrude "Z12_cut_circle (1)'" cut sketch "Z12_cut_circle (2)" along normal blind 12.1 bodies 12 in component "SpacerB"
sketch "Z13_cut_circle (2)" plane through (0, 0, -12) normal (0, 0, 1) x (1, 0, 0) in component "SpacerB"
  circle A0 centre (11.1, -26.8) radius 1.7
extrude "Z13_cut_circle (1)'" cut sketch "Z13_cut_circle (2)" along normal blind 12.1 bodies 12 in component "SpacerB"
ref_plane "WorkPlane5" through (0, 0, -7.7) normal (0, 0, 1) x (1, 0, 0) in component "SpacerB"
sketch "Z14_cut_hex" plane through (0, 0, -7.7) normal (0, 0, 1) x (1, 0, 0) in component "SpacerB"
  line L0 (28.8034, 13.7108) -> (25.5407, 14.1404)
  line L1 (25.5407, 14.1404) -> (23.5373, 11.5296)
  line L2 (23.5373, 11.5296) -> (24.7966, 8.4892)
  line L3 (24.7966, 8.4892) -> (28.0593, 8.0596)
  line L4 (28.0593, 8.0596) -> (30.0627, 10.6704)
  line L5 (30.0627, 10.6704) -> (28.8034, 13.7108)
extrude "Z14_cut_hex (1)" cut sketch "Z14_cut_hex" along normal blind 4.2 bodies 12 in component "SpacerB"
sketch "Z15_cut_poly" plane through (0, 0, -7.7) normal (0, 0, 1) x (1, 0, 0) in component "SpacerB"
  line L0 (25.7094, 13.7331) -> (53.4262, 25.2128)
  line L1 (53.4262, 25.2128) -> (55.6073, 19.9466)
  line L2 (55.6073, 19.9466) -> (27.8906, 8.4669)
  line L3 (27.8906, 8.4669) -> (25.7094, 13.7331)
extrude "Z15_cut_poly (1)" cut sketch "Z15_cut_poly" along normal blind 4.2 bodies 12 in component "SpacerB"
sketch "Z16_cut_hex" plane through (0, 0, -7.7) normal (0, 0, 1) x (1, 0, 0) in component "SpacerB"
  line L0 (-13.7108, 28.8034) -> (-14.1404, 25.5407)
  line L1 (-14.1404, 25.5407) -> (-11.5296, 23.5373)
  line L2 (-11.5296, 23.5373) -> (-8.4892, 24.7966)
  line L3 (-8.4892, 24.7966) -> (-8.0596, 28.0593)
  line L4 (-8.0596, 28.0593) -> (-10.6704, 30.0627)
  line L5 (-10.6704, 30.0627) -> (-13.7108, 28.8034)
extrude "Z16_cut_hex (1)" cut sketch "Z16_cut_hex" along normal blind 4.2 bodies 12 in component "SpacerB"
sketch "Z17_cut_poly" plane through (0, 0, -7.7) normal (0, 0, 1) x (1, 0, 0) in component "SpacerB"
  line L0 (-13.7331, 25.7094) -> (-25.2128, 53.4262)
  line L1 (-25.2128, 53.4262) -> (-19.9466, 55.6073)
  line L2 (-19.9466, 55.6073) -> (-8.4669, 27.8906)
  line L3 (-8.4669, 27.8906) -> (-13.7331, 25.7094)
extrude "Z17_cut_poly (1)" cut sketch "Z17_cut_poly" along normal blind 4.2 bodies 12 in component "SpacerB"
sketch "Z18_cut_hex" plane through (0, 0, -7.7) normal (0, 0, 1) x (1, 0, 0) in component "SpacerB"
  line L0 (-18.1307, -31.7883) -> (-15.2176, -30.2573)
  line L1 (-15.2176, -30.2573) -> (-15.0869, -26.969)
  line L2 (-15.0869, -26.969) -> (-17.8693, -25.2117)
  line L3 (-17.8693, -25.2117) -> (-20.7824, -26.7427)
  line L4 (-20.7824, -26.7427) -> (-20.9131, -30.031)
  line L5 (-20.9131, -30.031) -> (-18.1307, -31.7883)
extrude "Z18_cut_hex (1)" cut sketch "Z18_cut_hex" along normal blind 4.2 bodies 12 in component "SpacerB"
sketch "Z19_cut_poly" plane through (0, 0, -7.7) normal (0, 0, 1) x (1, 0, 0) in component "SpacerB"
  line L0 (-15.5904, -30.0219) -> (-31.6101, -55.3865)
  line L1 (-31.6101, -55.3865) -> (-36.4294, -52.3428)
  line L2 (-36.4294, -52.3428) -> (-20.4096, -26.9781)
  line L3 (-20.4096, -26.9781) -> (-15.5904, -30.0219)
extrude "Z19_cut_poly (1)" cut sketch "Z19_cut_poly" along normal blind 4.2 bodies 12 in component "SpacerB"
sketch "Z20_cut_hex" plane through (0, 0, -7.7) normal (0, 0, 1) x (1, 0, 0) in component "SpacerB"
  line L0 (13.7108, -28.8034) -> (14.1404, -25.5407)
  line L1 (14.1404, -25.5407) -> (11.5296, -23.5373)
  line L2 (11.5296, -23.5373) -> (8.4892, -24.7966)
  line L3 (8.4892, -24.7966) -> (8.0596, -28.0593)
  line L4 (8.0596, -28.0593) -> (10.6704, -30.0627)
  line L5 (10.6704, -30.0627) -> (13.7108, -28.8034)
extrude "Z20_cut_hex (1)" cut sketch "Z20_cut_hex" along normal blind 4.2 bodies 12 in component "SpacerB"
sketch "Z21_cut_poly" plane through (0, 0, -7.7) normal (0, 0, 1) x (1, 0, 0) in component "SpacerB"
  line L0 (13.7331, -25.7094) -> (25.2128, -53.4262)
  line L1 (25.2128, -53.4262) -> (19.9466, -55.6073)
  line L2 (19.9466, -55.6073) -> (8.4669, -27.8906)
  line L3 (8.4669, -27.8906) -> (13.7331, -25.7094)
extrude "Z21_cut_poly (1)" cut sketch "Z21_cut_poly" along normal blind 4.2 bodies 12 in component "SpacerB"
ref_plane "WorkPlane1" through (0, 0, -62) normal (0, 0, 1) x (1, 0, 0) in component "SpacerA"
sketch "Z00_add_circle (2)" plane through (0, 0, -62) normal (0, 0, 1) x (1, 0, 0) in component "SpacerA"
  circle A0 centre (0, 0) radius 32.15
extrude "Z00_add_circle (1)'" add sketch "Z00_add_circle (2)" along normal blind 27 separate body makes body 13 in component "SpacerA"
ref_plane "WorkPlane2" through (0, 0, -72.2) normal (0, 0, 1) x (1, 0, 0) in component "SpacerA"
sketch "Z01_add_circle" plane through (0, 0, -72.2) normal (0, 0, 1) x (1, 0, 0) in component "SpacerA"
  circle A0 centre (0, 0) radius 31.6
extrude "Z01_add_circle (1)" add sketch "Z01_add_circle" along normal blind 10.2 bodies 13 in component "SpacerA"
sketch "Z02_add_rect" plane through (0, 0, -62) normal (0, 0, 1) x (1, 0, 0) in component "SpacerA"
  line L0 (28, -17.5) -> (46.44, -17.5)
  line L1 (46.44, -17.5) -> (46.44, 17.5)
  line L2 (46.44, 17.5) -> (28, 17.5)
  line L3 (28, 17.5) -> (28, -17.5)
extrude "Z02_add_rect (1)" add sketch "Z02_add_rect" along normal blind 27 bodies 13 in component "SpacerA"
ref_plane "WorkPlane3" through (0, 0, -72.3) normal (0, 0, 1) x (1, 0, 0) in component "SpacerA"
sketch "Z03_cut_circle (4)" plane through (0, 0, -72.3) normal (0, 0, 1) x (1, 0, 0) in component "SpacerA"
  circle A0 centre (0, 0) radius 12.55
extrude "Z03_cut_circle (1)'''" cut sketch "Z03_cut_circle (4)" along normal blind 10.3 bodies 13 in component "SpacerA"
sketch "Z04_cut_circle (2)" plane through (0, 0, -72.3) normal (0, 0, 1) x (1, 0, 0) in component "SpacerA"
  circle A0 centre (23.097, -9.5671) radius 3.3
extrude "Z04_cut_circle (1)'" cut sketch "Z04_cut_circle (2)" along normal blind 37.4 bodies 13 in component "SpacerA"
sketch "Z05_cut_circle (2)" plane through (0, 0, -72.3) normal (0, 0, 1) x (1, 0, 0) in component "SpacerA"
  circle A0 centre (9.5671, 23.097) radius 3.3
extrude "Z05_cut_circle (1)'" cut sketch "Z05_cut_circle (2)" along normal blind 37.4 bodies 13 in component "SpacerA"
sketch "Z06_cut_circle (3)" plane through (0, 0, -72.3) normal (0, 0, 1) x (1, 0, 0) in component "SpacerA"
  circle A0 centre (-23.097, 9.5671) radius 3.3
extrude "Z06_cut_circle (1)''" cut sketch "Z06_cut_circle (3)" along normal blind 37.4 bodies 13 in component "SpacerA"
sketch "Z07_cut_circle (2)" plane through (0, 0, -72.3) normal (0, 0, 1) x (1, 0, 0) in component "SpacerA"
  circle A0 centre (-9.5671, -23.097) radius 3.3
extrude "Z07_cut_circle (1)'" cut sketch "Z07_cut_circle (2)" along normal blind 37.4 bodies 13 in component "SpacerA"
ref_plane "WorkPlane1" through (0, 0, -83.8) normal (0, 0, 1) x (1, 0, 0) in component "CameraMount"
sketch "Z00_add_circle (3)" plane through (0, 0, -83.8) normal (0, 0, 1) x (1, 0, 0) in component "CameraMount"
  circle A0 centre (0, 0) radius 35.7
extrude "Z00_add_circle (1)''" add sketch "Z00_add_circle (3)" along normal blind 11.6 separate body makes body 14 in component "CameraMount"
sketch "Z01_add_rect (2)" plane through (0, 0, -83.8) normal (0, 0, 1) x (1, 0, 0) in component "CameraMount"
  line L0 (0, -29.57) -> (107.1, -29.57)
  line L1 (107.1, -29.57) -> (107.1, 29.57)
  line L2 (107.1, 29.57) -> (0, 29.57)
  line L3 (0, 29.57) -> (0, -29.57)
extrude "Z01_add_rect (1)'" add sketch "Z01_add_rect (2)" along normal blind 11.6 bodies 14 in component "CameraMount"
ref_plane "WorkPlane2" through (0, 0, -83.9) normal (0, 0, 1) x (1, 0, 0) in component "CameraMount"
sketch "Z04_cut_circle (3)" plane through (0, 0, -83.9) normal (0, 0, 1) x (1, 0, 0) in component "CameraMount"
  circle A0 centre (0, 0) radius 31.6
extrude "Z04_cut_circle (1)''" cut sketch "Z04_cut_circle (3)" along normal blind 6.7 bodies 14 in component "CameraMount"
ref_plane "WorkPlane3" through (0, 0, -77.3) normal (0, 0, 1) x (1, 0, 0) in component "CameraMount"
sketch "Z05_cut_circle (3)" plane through (0, 0, -77.3) normal (0, 0, 1) x (1, 0, 0) in component "CameraMount"
  circle A0 centre (0, 0) radius 16.05
extrude "Z05_cut_circle (1)''" cut sketch "Z05_cut_circle (3)" along normal blind 5.2 bodies 14 in component "CameraMount"
sketch "Z06_cut_circle (4)" plane through (0, 0, -83.9) normal (0, 0, 1) x (1, 0, 0) in component "CameraMount"
  circle A0 centre (23.097, -9.5671) radius 3.3
extrude "Z06_cut_circle (1)'''" cut sketch "Z06_cut_circle (4)" along normal blind 11.8 bodies 14 in component "CameraMount"
sketch "Z07_cut_circle (3)" plane through (0, 0, -83.9) normal (0, 0, 1) x (1, 0, 0) in component "CameraMount"
  circle A0 centre (9.5671, 23.097) radius 3.3
extrude "Z07_cut_circle (1)''" cut sketch "Z07_cut_circle (3)" along normal blind 11.8 bodies 14 in component "CameraMount"
sketch "Z08_cut_circle (2)" plane through (0, 0, -83.9) normal (0, 0, 1) x (1, 0, 0) in component "CameraMount"
  circle A0 centre (-23.097, 9.5671) radius 3.3
extrude "Z08_cut_circle (1)'" cut sketch "Z08_cut_circle (2)" along normal blind 11.8 bodies 14 in component "CameraMount"
sketch "Z09_cut_circle (3)" plane through (0, 0, -83.9) normal (0, 0, 1) x (1, 0, 0) in component "CameraMount"
  circle A0 centre (-9.5671, -23.097) radius 3.3
extrude "Z09_cut_circle (1)''" cut sketch "Z09_cut_circle (3)" along normal blind 11.8 bodies 14 in component "CameraMount"
sketch "Z10_cut_circle (2)" plane through (0, 0, -83.9) normal (0, 0, 1) x (1, 0, 0) in component "CameraMount"
  circle A0 centre (-23.097, -9.5671) radius 3.175
extrude "Z10_cut_circle (1)'" cut sketch "Z10_cut_circle (2)" along normal blind 11.8 bodies 14 in component "CameraMount"
sketch "Z11_cut_circle (2)" plane through (0, 0, -83.9) normal (0, 0, 1) x (1, 0, 0) in component "CameraMount"
  circle A0 centre (100.36, 22.41) radius 1.7
extrude "Z11_cut_circle (1)'" cut sketch "Z11_cut_circle (2)" along normal blind 11.8 bodies 14 in component "CameraMount"
sketch "Z12_cut_circle (3)" plane through (0, 0, -83.9) normal (0, 0, 1) x (1, 0, 0) in component "CameraMount"
  circle A0 centre (100.36, -22.59) radius 1.7
extrude "Z12_cut_circle (1)''" cut sketch "Z12_cut_circle (3)" along normal blind 11.8 bodies 14 in component "CameraMount"
sketch "Z13_cut_circle (3)" plane through (0, 0, -83.9) normal (0, 0, 1) x (1, 0, 0) in component "CameraMount"
  circle A0 centre (100.36, 22.41) radius 3.1
extrude "Z13_cut_circle (1)''" cut sketch "Z13_cut_circle (3)" along normal blind 7.2 bodies 14 in component "CameraMount"
sketch "Z14_cut_circle (2)" plane through (0, 0, -83.9) normal (0, 0, 1) x (1, 0, 0) in component "CameraMount"
  circle A0 centre (100.36, -22.59) radius 3.1
extrude "Z14_cut_circle (1)'" cut sketch "Z14_cut_circle (2)" along normal blind 7.2 bodies 14 in component "CameraMount"
ref_plane "WorkPlane1" through (0, 0, -72.2) normal (0, 0, 1) x (1, 0, 0) in component "RealSense_D435i_Ref"
sketch "Z00_add_rect" plane through (0, 0, -72.2) normal (0, 0, 1) x (1, 0, 0) in component "RealSense_D435i_Ref"
  line L0 (87.85, -45.1) -> (112.85, -45.1)
  line L1 (112.85, -45.1) -> (112.85, 44.9)
  line L2 (112.85, 44.9) -> (87.85, 44.9)
  line L3 (87.85, 44.9) -> (87.85, -45.1)
extrude "Z00_add_rect (1)" add sketch "Z00_add_rect" along normal blind 25 separate body makes body 15 in component "RealSense_D435i_Ref"
ref_plane "WorkPlane8" through (7.75, 0, 0) normal (1, 0, 0) x (0, 1, 0) in component "Tower"
sketch "HW_M3x30_PivotO_L_0" plane through (7.75, 0, 0) normal (1, 0, 0) x (0, 0, -1) in component "Tower"
  circle A0 centre (-54.905, -30.601) radius 2.75
extrude "HW_M3x30_PivotO_L_0 (1)" add sketch "HW_M3x30_PivotO_L_0" along normal blind 3 separate body makes body 16 in component "Tower"
ref_plane "WorkPlane9" through (-22.25, 0, 0) normal (1, 0, 0) x (0, 1, 0) in component "Tower"
sketch "HW_M3x30_PivotO_L_1" plane through (-22.25, 0, 0) normal (1, 0, 0) x (0, 0, -1) in component "Tower"
  circle A0 centre (-54.905, -30.601) radius 1.45
extrude "HW_M3x30_PivotO_L_1 (1)" add sketch "HW_M3x30_PivotO_L_1" along normal blind 30 bodies 16 in component "Tower"
ref_plane "WorkPlane10" through (-15.5, 0, 0) normal (1, 0, 0) x (0, 1, 0) in component "Tower"
sketch "HW_M3x30_PivotO_L_2" plane through (-15.5, 0, 0) normal (1, 0, 0) x (0, 0, -1) in component "Tower"
  circle A0 centre (-54.905, -30.601) radius 3.2
extrude "HW_M3x30_PivotO_L_2 (1)" add sketch "HW_M3x30_PivotO_L_2" along normal blind 4 bodies 16 in component "Tower"
ref_plane "WorkPlane11" through (-11.5, 0, 0) normal (1, 0, 0) x (0, 1, 0) in component "Tower"
sketch "HW_M3x30_PivotO_L_3" plane through (-11.5, 0, 0) normal (1, 0, 0) x (0, 0, -1) in component "Tower"
  circle A0 centre (-54.905, -30.601) radius 3.5
extrude "HW_M3x30_PivotO_L_3 (1)" add sketch "HW_M3x30_PivotO_L_3" along normal blind 0.5 bodies 16 in component "Tower"
ref_plane "WorkPlane12" through (-10.75, 0, 0) normal (1, 0, 0) x (0, 1, 0) in component "Tower"
sketch "HW_M3x30_PivotO_R_0" plane through (-10.75, 0, 0) normal (1, 0, 0) x (0, 0, -1) in component "Tower"
  circle A0 centre (-54.905, 30.601) radius 2.75
extrude "HW_M3x30_PivotO_R_0 (1)" add sketch "HW_M3x30_PivotO_R_0" along normal blind 3 separate body makes body 17 in component "Tower"
ref_plane "WorkPlane13" through (-7.75, 0, 0) normal (1, 0, 0) x (0, 1, 0) in component "Tower"
sketch "HW_M3x30_PivotO_R_1" plane through (-7.75, 0, 0) normal (1, 0, 0) x (0, 0, -1) in component "Tower"
  circle A0 centre (-54.905, 30.601) radius 1.45
extrude "HW_M3x30_PivotO_R_1 (1)" add sketch "HW_M3x30_PivotO_R_1" along normal blind 30 bodies 17 in component "Tower"
ref_plane "WorkPlane14" through (11.5, 0, 0) normal (1, 0, 0) x (0, 1, 0) in component "Tower"
sketch "HW_M3x30_PivotO_R_2" plane through (11.5, 0, 0) normal (1, 0, 0) x (0, 0, -1) in component "Tower"
  circle A0 centre (-54.905, 30.601) radius 3.2
extrude "HW_M3x30_PivotO_R_2 (1)" add sketch "HW_M3x30_PivotO_R_2" along normal blind 4 bodies 17 in component "Tower"
ref_plane "WorkPlane15" through (11, 0, 0) normal (1, 0, 0) x (0, 1, 0) in component "Tower"
sketch "HW_M3x30_PivotO_R_3" plane through (11, 0, 0) normal (1, 0, 0) x (0, 0, -1) in component "Tower"
  circle A0 centre (-54.905, 30.601) radius 3.5
extrude "HW_M3x30_PivotO_R_3 (1)" add sketch "HW_M3x30_PivotO_R_3" along normal blind 0.5 bodies 17 in component "Tower"
ref_plane "WorkPlane16" through (-22.5, 0, 0) normal (1, 0, 0) x (0, 1, 0) in component "Tower"
ref_plane "WorkPlane17" through (-19.5, 0, 0) normal (1, 0, 0) x (0, 1, 0) in component "Tower"
ref_plane "WorkPlane18" through (19.5, 0, 0) normal (1, 0, 0) x (0, 1, 0) in component "Tower"
ref_plane "WorkPlane19" through (19, 0, 0) normal (1, 0, 0) x (0, 1, 0) in component "Tower"
ref_plane "WorkPlane20" through (-25.5, 0, 0) normal (1, 0, 0) x (0, 1, 0) in component "Tower"
ref_plane "WorkPlane21" through (-23.5, 0, 0) normal (1, 0, 0) x (0, 1, 0) in component "Tower"
ref_plane "WorkPlane4" through (-15.5, 0, 0) normal (1, 0, 0) x (0, 1, 0) in component "OuterFinger"
sketch "HW_M3x30_J_0" plane through (-15.5, 0, 0) normal (1, 0, 0) x (0, 0, -1) in component "OuterFinger"
  circle A0 centre (-51.2999, -62.1457) radius 2.75
extrude "HW_M3x30_J_0 (1)" add sketch "HW_M3x30_J_0" along normal blind 3 separate body makes body 18 in component "OuterFinger"
ref_plane "WorkPlane5" through (-12.5, 0, 0) normal (1, 0, 0) x (0, 1, 0) in component "OuterFinger"
sketch "HW_M3x30_J_1" plane through (-12.5, 0, 0) normal (1, 0, 0) x (0, 0, -1) in component "OuterFinger"
  circle A0 centre (-51.2999, -62.1457) radius 1.45
extrude "HW_M3x30_J_1 (1)" add sketch "HW_M3x30_J_1" along normal blind 30 bodies 18 in component "OuterFinger"
ref_plane "WorkPlane6" through (12.5, 0, 0) normal (1, 0, 0) x (0, 1, 0) in component "OuterFinger"
sketch "HW_M3x30_J_2" plane through (12.5, 0, 0) normal (1, 0, 0) x (0, 0, -1) in component "OuterFinger"
  circle A0 centre (-51.2999, -62.1457) radius 3.2
extrude "HW_M3x30_J_2 (1)" add sketch "HW_M3x30_J_2" along normal blind 4 bodies 18 in component "OuterFinger"
sketch "HW_M3x30_J_3" plane through (-12.5, 0, 0) normal (1, 0, 0) x (0, 0, -1) in component "OuterFinger"
  circle A0 centre (-51.2999, -62.1457) radius 3.5
extrude "HW_M3x30_J_3 (1)" add sketch "HW_M3x30_J_3" along normal blind 0.5 bodies 18 in component "OuterFinger"
ref_plane "WorkPlane7" through (12, 0, 0) normal (1, 0, 0) x (0, 1, 0) in component "OuterFinger"
sketch "HW_M3x30_J_4" plane through (12, 0, 0) normal (1, 0, 0) x (0, 0, -1) in component "OuterFinger"
  circle A0 centre (-51.2999, -62.1457) radius 3.5
extrude "HW_M3x30_J_4 (1)" add sketch "HW_M3x30_J_4" along normal blind 0.5 bodies 18 in component "OuterFinger"
sketch "HW_M3x30_J2_0" plane through (-15.5, 0, 0) normal (1, 0, 0) x (0, 0, -1) in component "OuterFinger"
  circle A0 centre (-60.539, -65.9718) radius 2.75
extrude "HW_M3x30_J2_0 (1)" add sketch "HW_M3x30_J2_0" along normal blind 3 separate body makes body 19 in component "OuterFinger"
sketch "HW_M3x30_J2_1" plane through (-12.5, 0, 0) normal (1, 0, 0) x (0, 0, -1) in component "OuterFinger"
  circle A0 centre (-60.539, -65.9718) radius 1.45
extrude "HW_M3x30_J2_1 (1)" add sketch "HW_M3x30_J2_1" along normal blind 30 bodies 19 in component "OuterFinger"
sketch "HW_M3x30_J2_2" plane through (12.5, 0, 0) normal (1, 0, 0) x (0, 0, -1) in component "OuterFinger"
  circle A0 centre (-60.539, -65.9718) radius 3.2
extrude "HW_M3x30_J2_2 (1)" add sketch "HW_M3x30_J2_2" along normal blind 4 bodies 19 in component "OuterFinger"
sketch "HW_M3x30_J2_3" plane through (-12.5, 0, 0) normal (1, 0, 0) x (0, 0, -1) in component "OuterFinger"
  circle A0 centre (-60.539, -65.9718) radius 3.5
extrude "HW_M3x30_J2_3 (1)" add sketch "HW_M3x30_J2_3" along normal blind 0.5 bodies 19 in component "OuterFinger"
sketch "HW_M3x30_J2_4" plane through (12, 0, 0) normal (1, 0, 0) x (0, 0, -1) in component "OuterFinger"
  circle A0 centre (-60.539, -65.9718) radius 3.5
extrude "HW_M3x30_J2_4 (1)" add sketch "HW_M3x30_J2_4" along normal blind 0.5 bodies 19 in component "OuterFinger"